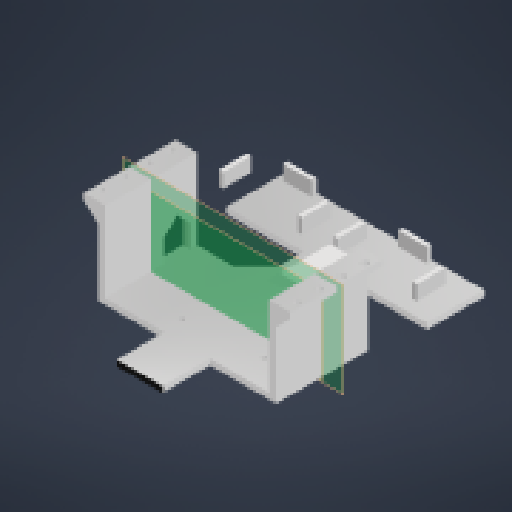
# Autodesk Inventor part: 01_4_1_support_electronique
Saved by Autodesk Inventor 2026 (Build 300175050, 175E)
## iProperties
Created: 2025-05-12
Part Number: 01_4_1_support_electronique
Material: Générique
Document SubType Name: Modeling
Designer: virgi
Density: 1 g/cm^3
Appearance: Par défaut
Author: virgi
Autodesk Inventor part; units mm, degrees
ref_plane "YZ Plane" through (0, 0, 0) normal (1, 0, 0) x (0, 1, 0)
ref_plane "XZ Plane" through (0, 0, 0) normal (0, 1, 0) x (-1, 0, 0)
ref_plane "XY Plane" through (0, 0, 0) normal (0, 0, 1) x (1, 0, 0)
sketch "Esquisse1" plane through (0, 0, 0) normal (0, 0, 1) x (1, 0, 0)
  line L0 (-46, 0) -> (-46, 56)
  line L1 (-46, 56) -> (-56, 56)
  line L2 (-56, 56) -> (-56, 60)
  line L3 (-56, 60) -> (-41, 60)
  line L4 (-41, 60) -> (-41, 4)
  line L5 (-41, 4) -> (0, 4)
  line L6 (-46, 0) -> (0, 0)
  line L7 (0, 42.9233) -> (0, -30.8476)
  line L8 (46, 0) -> (46, 56)
  line L9 (46, 56) -> (56, 56)
  line L10 (56, 56) -> (56, 60)
  line L11 (56, 60) -> (41, 60)
  line L12 (41, 60) -> (41, 4)
  line L13 (41, 4) -> (0, 4)
  line L14 (46, 0) -> (0, 0)
  line L15 (-52, 54.7729) -> (-52, 42.7626)
  line L16 (52, 54.7729) -> (52, 42.7626)
  dimension "d0" = 10
  dimension "d1" = 4
  dimension "d2" = 5
  dimension "d3" = 4
  dimension "d8" = 60
  dimension "d20" = 8
  dimension "d22" = 104
  constraints: 34 end point, 8 symmetric about line, 6 perpendicular, 2 vertical, 1 horizontal, 1 point on line
  measures "d0" distance between parallel lines of L0 L2
  measures "d1" distance between parallel lines of L6 L5
  measures "d2" distance between parallel lines of L0 L4
  measures "d3" distance between parallel lines of L1 L3
  measures "d8" distance between parallel lines of L6 L3
  measures "d20" diameter of L2 L15
  measures "d22" distance between parallel lines of L16 L15
extrude "Extrusion1" add sketch "Esquisse1" along normal blind 64
ref_plane "Plan de construction1" through (0, 0, 32) normal (0, 0, -1) x (-1, 0, 0)
sketch "Esquisse5" plane through (0, 0, 32) normal (0, 0, -1) x (-1, 0, 0)
  line L0 (0, 15.3323) -> (0, -9.4755) construction
  line L1 (0, 4) -> (-16, 4)
  line L2 (-16, 4) -> (-16, 0)
  line L3 (-16, 0) -> (0, 0)
  line L4 (0, 4) -> (16, 4)
  line L5 (16, 4) -> (16, 0)
  line L6 (16, 0) -> (0, 0)
  line L7 (46, 0) -> (-46, 0) projected
  point P0 (0, 0)
  dimension "d31" = 16
  dimension "d32" = 4
  constraints: 14 end point, 2 perpendicular, 2 point on line, 2 symmetric about line, 1 horizontal, 1 midpoint, 1 vertical
  measures "d31" distance between parallel lines of L2 L0
  measures "d32" distance between parallel lines of L6 L4
extrude "Extrusion3" add sketch "Esquisse5" along normal mid plane 130
sketch "Esquisse6" plane through (41, 60, 0) normal (0, 1, 0) x (1, 0, 0)
  line L0 (15, 0) -> (15, -64) projected
  line L1 (-119.4, -32) -> (37.4, -32) projected
  point P0 (-41, 0)
  point P1 (11, -56)
  dimension "d42" = 4
  dimension "d43" = 24
  measures "d42" distance from line of L0 point (11, -56)
  measures "d43" distance from line of L1 point (11, -56)
hole "Perçage2" at (52, 60, 56) direction (0, -1, 0) diameter 4.5 end through all
pattern_linear "Réseau rectangulaire2" count 4 spacing 16 along (0, 0, -1) count 2 spacing 104 along (-1, 0, 0) of "Perçage2"
sketch "Esquisse8" plane through (-41, 4, 64) normal (0, 1, 0) x (1, 0, 0)
  line L0 (111, 97) -> (-29, 97)
  line L1 (-29, 97) -> (-29, 137)
  line L2 (-29, 137) -> (111, 137)
  line L3 (111, 137) -> (111, 97)
  line L4 (25, 97) -> (57, 97) projected
  line L5 (51.5767, 32) -> (138.5024, 32) construction
  line L6 (82, 64) -> (57, 64) construction
  line L7 (78, 37) -> (78, 27) construction
  point P0 (41, 64)
  point P1 (78, 32)
  point P2 (-29, -33)
  dimension "d61" = 140
  dimension "d62" = 40
  dimension "d63" = 70
  constraints: 10 end point, 2 horizontal, 2 parallel, 2 point on line, 1 midpoint, 1 perpendicular, 1 symmetric about line
  measures "d61" distance between parallel lines of L1 L3
  measures "d62" distance of L2.end L0.start
  measures "d63" distance from line of L3 point (41, 64)
extrude "Extrusion5" add sketch "Esquisse8" against normal blind 4
sketch "Esquisse11" plane through (-41, 4, 64) normal (0, 1, 0) x (1, 0, 0)
  line L0 (106, 102) -> (106, 132) construction
  line L1 (106, 132) -> (56, 132) construction
  line L2 (56, 132) -> (56, 102) construction
  line L3 (106, 102) -> (56, 102) construction
  line L4 (57, 97) -> (111, 97) construction
  line L5 (111, 97) -> (111, 137) construction
  line L6 (110, 127) -> (107, 127)
  line L7 (107, 127) -> (107, 107)
  line L8 (107, 107) -> (110, 107)
  line L9 (110, 107) -> (110, 127)
  line L10 (91, 101) -> (71, 101)
  line L11 (71, 101) -> (71, 98)
  line L12 (71, 98) -> (91, 98)
  line L13 (91, 98) -> (91, 101)
  line L14 (55, 127) -> (52, 127)
  line L15 (52, 127) -> (52, 107)
  line L16 (52, 107) -> (55, 107)
  line L17 (55, 107) -> (55, 127)
  line L18 (91, 136) -> (71, 136)
  line L19 (71, 136) -> (71, 133)
  line L20 (71, 133) -> (91, 133)
  line L21 (91, 133) -> (91, 136)
  line L22 (41, 143.1339) -> (41, -78.841) construction
  line L23 (-24, 102) -> (-24, 132) construction
  line L24 (-24, 132) -> (26, 132) construction
  line L25 (26, 132) -> (26, 102) construction
  line L26 (-24, 102) -> (26, 102) construction
  line L27 (25, 97) -> (-29, 97) construction
  line L28 (-29, 97) -> (-29, 137) construction
  line L29 (-28, 127) -> (-25, 127)
  line L30 (-25, 127) -> (-25, 107)
  line L31 (-25, 107) -> (-28, 107)
  line L32 (-28, 107) -> (-28, 127)
  line L33 (-9, 101) -> (11, 101)
  line L34 (11, 101) -> (11, 98)
  line L35 (11, 98) -> (-9, 98)
  line L36 (-9, 98) -> (-9, 101)
  line L37 (27, 127) -> (30, 127)
  line L38 (30, 127) -> (30, 107)
  line L39 (30, 107) -> (27, 107)
  line L40 (27, 107) -> (27, 127)
  line L41 (-9, 136) -> (11, 136)
  line L42 (11, 136) -> (11, 133)
  line L43 (11, 133) -> (-9, 133)
  line L44 (-9, 133) -> (-9, 136)
  line L45 (46, 68) -> (36, 68) construction
  line L46 (111, 137) -> (-29, 137) construction
  point P0 (41, 64)
  point P1 (106, 117)
  point P2 (81, 102)
  point P3 (-24, 117)
  point P4 (1, 102)
  point P5 (41, 68)
  point P6 (41, 137)
  dimension "d80" = 5
  dimension "d81" = 5
  dimension "d82" = 30
  dimension "d83" = 50
  dimension "d84" = 3
  dimension "d85" = 3
  dimension "d88" = 20
  dimension "d89" = 10
  dimension "d90" = 10
  dimension "d91" = 20
  dimension "d92" = 1
  dimension "d93" = 1
  dimension "d94" = 1
  dimension "d95" = 1
  constraints: 86 end point, 25 symmetric about line, 10 point on line, 8 parallel, 6 perpendicular, 5 horizontal, 4 midpoint, 2 collinear, 2 vertical
  measures "d80" distance between parallel lines of L3 L4
  measures "d81" distance between parallel lines of L5 L0
  measures "d82" distance between parallel lines of L1 L3
  measures "d83" distance between parallel lines of L2 L0
  measures "d84" distance between parallel lines of L7 L9
  measures "d85" distance between parallel lines of L10 L12
  measures "d88" distance between parallel lines of L8 L6
  measures "d89" distance from line of point (106, 117) L6
  measures "d90" distance from line of point (81, 102) L13
  measures "d91" distance between parallel lines of L13 L11
  measures "d92" distance between parallel lines of L1 L20
  measures "d93" distance between parallel lines of L2 L17
  measures "d94" distance between parallel lines of L3 L10
  measures "d95" distance between parallel lines of L0 L7
extrude "Extrusion8" add sketch "Esquisse11" along normal blind 10 contours L9 L8 L7 L6 | L17 L16 L15 L14 | L21 L20 L19 L18 | L29 L30 L31 L32 | L37 L38 L39 L40 | L41 L42 L43 L44
sketch "Esquisse12" plane through (-46, 0, 0) normal (-1, 0, 0) x (0, 0, 1)
  line L0 (5, 29) -> (23, 29)
  line L1 (23, 29) -> (23, 4)
  line L2 (23, 4) -> (5, 4)
  line L3 (5, 4) -> (5, 29)
  line L4 (5, 29) -> (23, 4) construction
  line L5 (23, 29) -> (5, 4) construction
  point P0 (0, 0)
  point P1 (14, 16.5)
  point P2 (0, 4)
  dimension "d99" = 18
  dimension "d101" = 5
  dimension "d107" = 25
  constraints: 12 end point, 2 midpoint, 2 parallel, 1 horizontal, 1 perpendicular, 1 point on line
  measures "d99" distance between parallel lines of L1 L3
  measures "d101" distance from line of point (0, 4) L3
  measures "d107" distance between parallel lines of L2 L0
extrude "Extrusion9" cut sketch "Esquisse12" against normal blind 10
ref_plane "Plan de construction3" through (0, 0, 32) normal (0, 0, -1) x (-1, 0, 0)
sketch "Esquisse14" plane through (0, 0, 32) normal (0, 0, -1) x (-1, 0, 0)
  line L0 (46, 46) -> (56, 56)
  line L1 (46, 46) -> (46, 56)
  line L2 (46, 56) -> (56, 56)
  point P0 (0, 0)
  dimension "d104" = 45
  constraints: 6 end point, 2 point on line, 1 perpendicular, 1 vertical
  measures "d104" angle of L1 L0
extrude "Extrusion10" add sketch "Esquisse14" along normal mid plane 3
chamfer "Chanfrein1" distance 9 angle 45 2 edges at (-43.5, 29, 23) (-43.5, 29, 5)
pattern_linear "Réseau rectangulaire3" count 5 spacing 15.25 along (0, 0, 1) of "Extrusion10" first direction both ways yes
mirror "Mise en miroir1" about plane through (0, 0, 0) normal (1, 0, 0) of "Extrusion10"
mirror "Mise en miroir2" about plane through (0, 0, 0) normal (1, 0, 0) of "Extrusion10", "Réseau rectangulaire3"
chamfer "Chanfrein2" distance 2 angle 45 20 edges at (46, 56, 54.875) (51, 56, 48.75) (51, 56, 33.5) (46, 56, 39.625) (51, 56, 45.75) (51, 56, 30.5) (46, 56, 24.375) (51, 56, 18.25) (46, 56, 9.125) (51, 56, 15.25) (-46, 56, 9.125) (-46, 56, 24.375) (-46, 56, 39.625) (-46, 56, 54.875) (-51, 56, 33.5) (-51, 56, 30.5) (-51, 56, 18.25) (-51, 56, 45.75) (-51, 56, 48.75) (-51, 56, 15.25)
sketch "Esquisse17" plane through (41, 4, 64) normal (0, 1, 0) x (1, 0, 0)
  line L0 (-57, 0) -> (-57, -33) projected
  line L1 (-57, 0) -> (-82, 0) projected
  line L2 (0, 64) -> (0, 0) projected
  line L3 (0, 0) -> (-25, 0) projected
  point P0 (-41, 64)
  point P1 (-59, 14)
  point P2 (-6.93, 19.08)
  dimension "d127" = 2
  dimension "d128" = 14
  dimension "d132" = 52.07
  dimension "d133" = 5.08
  measures "d127" distance from line of point (-59, 14) L0
  measures "d128" distance from line of point (-59, 14) L1
  measures "d132" horizontal distance of point (-6.93, 19.08) point (-59, 14)
  measures "d133" vertical distance of point (-6.93, 19.08) point (-59, 14)
hole "Perçage3" at (-18, 4, 50) at (34.07, 4, 44.92) direction (0, -1, 0) diameter 3.5 end through all
chamfer "Chanfrein3" distance 15 angle 45 2 edges at (-16, 2, 0) (16, 2, 0)
sketch "Esquisse18" plane through (41, 4, 64) normal (0, 1, 0) x (1, 0, 0)
  line L0 (-33.5, 107) -> (-48.5, 107)
  line L1 (-48.5, 107) -> (-48.5, 72)
  line L2 (-48.5, 72) -> (-33.5, 72)
  line L3 (-33.5, 72) -> (-33.5, 107)
  line L4 (-25, 79) -> (-25, 97) projected
  line L5 (-57, 97) -> (-57, 79) projected
  point P0 (-41, 64)
  point P1 (-30, 107)
  dimension "d137" = 35
  dimension "d138" = 15
  dimension "d141" = 8.5
  constraints: 8 end point, 2 parallel, 1 horizontal, 1 perpendicular, 1 point on line
  measures "d137" distance between parallel lines of L0 L2
  measures "d138" distance of L1.end L2.end
  measures "d141" distance between parallel lines of L3 L4
extrude "Extrusion11" add sketch "Esquisse18" along normal blind 4
chamfer "Chanfrein4" distance 4 angle 45 4 edges at (-7.5, 4, -25.5) (0, 4, -43) (7.5, 4, -25.5) (0, 4, -8)
